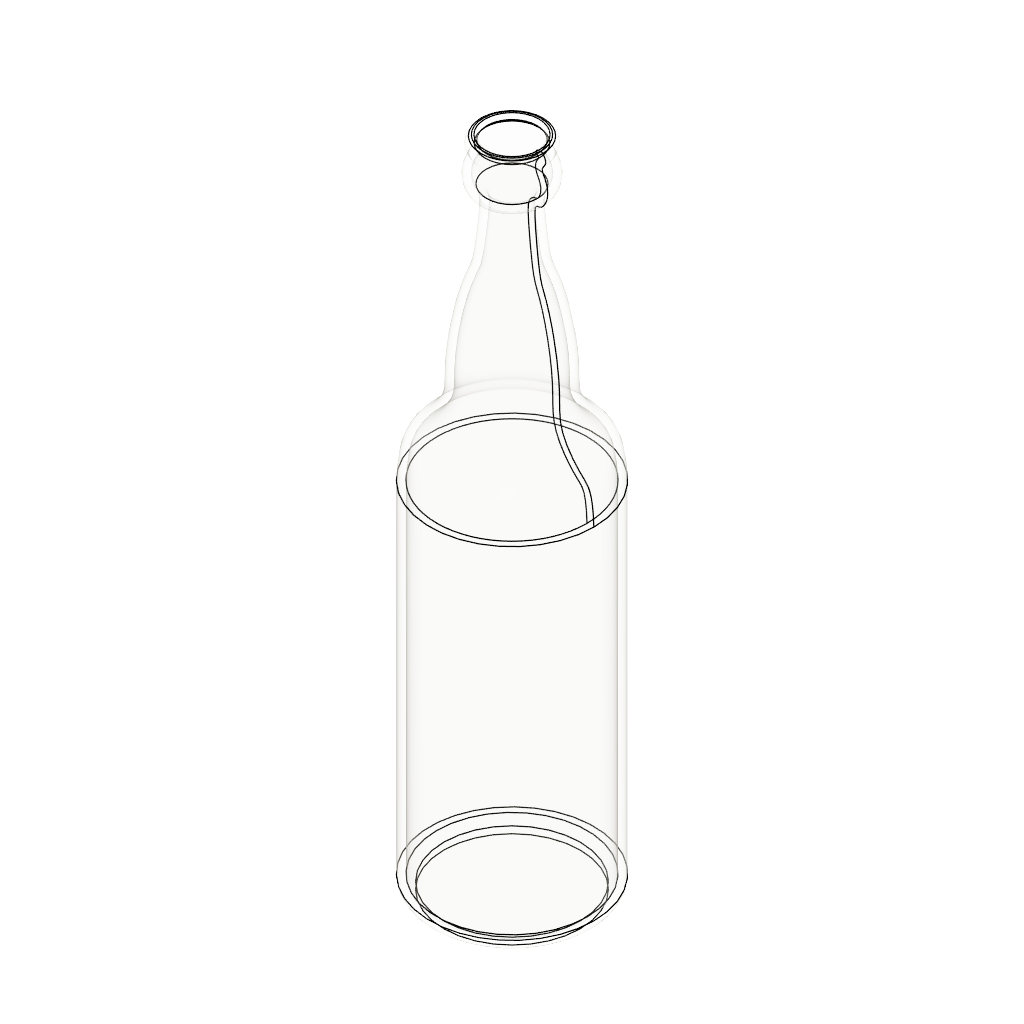
CAD2Bottle (Autodesk Fusion 360 design; units mm, degrees)
part number: 2026-09-26-20-24-34-349
Autodesk Fusion 360 part; units mm, degrees
sketch "Sketch1" plane through (0, 0, 0) normal (0, 0, 1) x (1, 0, 0)
  line L0 (0, 0) -> (0, 239.5972)
  line L1 (0, 0) -> (30, 0)
  line L2 (30, 0) -> (30, 130)
  spline S0 degree 5 poles (30, 130) (29.9707, 130.8832) (29.8961, 132.5679) (29.7369, 134.8498) (29.4296, 137.4018) (28.883, 139.8043) (28.1623, 141.5129) (27.2443, 142.7206) (26.0921, 143.7455) (24.6442, 145.0966) (22.9996, 146.8926) (21.3285, 149.0643) (19.8284, 151.4254) (18.6675, 153.7867) (17.9243, 156.068) (17.5584, 158.3556) (17.4563, 160.8197) (17.461, 163.662) (17.4076, 167.0515) (17.1562, 171.0652) (16.627, 175.6257) (15.832, 180.444) (14.8455, 185.1296) (13.7777, 189.2841) (12.7454, 192.6199) (11.8494, 195.0259) (11.1354, 196.7554) (10.5941, 198.3308) (10.0635, 201.1471) (9.4892, 205.5049) (8.9284, 210.7387) (8.4961, 215.8059) (8.3305, 219.5839) (8.5679, 221.4852) (9.2711, 221.4899) (10.4792, 221.5055) (11.8856, 222.7746) (12.9774, 225.0667) (13.3212, 227.7439) (12.833, 230.1255) (11.9197, 231.9802) (11.1366, 233.304) (10.9586, 234.2646) (11.4547, 235.0722) (12.1606, 235.9028) (12.5137, 236.8876) (12.2781, 237.851) (11.7686, 238.682) (11.2809, 239.2841) (11, 239.5972) knots 0 0 0 0 0 0 0.022222 0.044444 0.066667 0.088889 0.111111 0.133333 0.155556 0.177778 0.2 0.222222 0.244444 0.266667 0.288889 0.311111 0.333333 0.355556 0.377778 0.4 0.422222 0.444444 0.466667 0.488889 0.511111 0.533333 0.555556 0.577778 0.6 0.622222 0.644444 0.666667 0.688889 0.711111 0.733333 0.755556 0.777778 0.8 0.822222 0.844444 0.866667 0.888889 0.911111 0.933333 0.955556 0.977778 1 1 1 1 1 1
  line L3 (6.5287, 220.9303) -> (12, 222)
  line L4 (12.6428, 191.2532) -> (8.8686, 204.7894)
  line L5 (32, 138) -> (21.3698, 148.387)
  line L6 (0, 239.5972) -> (11, 239.5972)
  point P0 (26.6849, 143.1935)
  point P1 (19.1057, 153)
  point P2 (17.1057, 171)
  point P3 (10.7557, 198.0213)
  point P4 (9.2643, 221.4652)
  point P5 (13.1057, 227)
  point P6 (11.1057, 234)
  point P7 (12.1057, 236)
  dimension "d1" = 30
  dimension "d2" = 130
  dimension "d3" = 11
  constraint coincident L0.start L1.start
  constraint vertical L0
  constraint perpendicular L0 L1
  constraint perpendicular L1 L2
  constraint midpoint P4 L3
  constraint midpoint P3 L4
  constraint midpoint P0 L5
  constraint perpendicular L0 L6
  constraint coincident S0.end L6.end
  measures "d1" distance of L0.start L1.end
  measures "d2" distance of L1.end L2.end
  measures "d3" distance of L0.end S0.end
revolve "Revolve1" add sketch "Sketch1" angle 360 about axis through (0, 0, 0) along (0, 1, 0) contours L0 L1 L2 S0 L3 L6 | S0 L3
fillet "Fillet1" radius 5 1 faces at (14.141, 0, 6.0737)
shell "Shell1" thickness 2.5 removed faces 1 at (-0.8159, 239.5972, 0.3929)
fillet "Fillet2" radius 1 2 edges at (-10.2556, 239.5972, -3.9778) (-7.6414, 239.5972, 0.0038)
